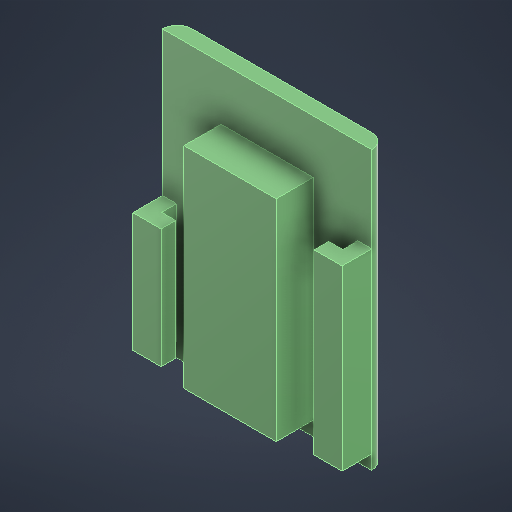
# Autodesk Inventor part: Tapa pulgar
Saved by Autodesk Inventor 2026 (Build 300175050, 175E)
## iProperties
Created: 2026-04-23
Part Number: Tapa pulgar
Material: Plástico ABS
Document SubType Name: Modeling
Designer: thepr
Density: 1.06 g/cm^3
Appearance: Suave - Verde bosque oscuro
Author: thepr
Autodesk Inventor part; units mm, degrees
ref_plane "YZ Plane" through (0, 0, 0) normal (1, 0, 0) x (0, 1, 0)
ref_plane "XZ Plane" through (0, 0, 0) normal (0, 1, 0) x (-1, 0, 0)
ref_plane "XY Plane" through (0, 0, 0) normal (0, 0, 1) x (1, 0, 0)
sketch "Boceto1" plane through (0, 0, 0) normal (0, 0, 1) x (1, 0, 0)
  line L0 (0, 0) -> (28.25, 0)
  line L1 (28.25, 0) -> (28.25, 37.5)
  line L2 (28.25, 37.5) -> (0, 37.5)
  line L3 (0, 37.5) -> (0, 0)
  line L4 (2, 37.5) -> (2, 0)
  line L5 (2, 2) -> (28.25, 2)
  line L6 (26.25, 37.5) -> (26.25, 2)
  line L7 (2, 35.5) -> (26.25, 35.5)
  dimension "d0" = 37.5
  dimension "d1" = 28.25
  dimension "d2" = 2
  dimension "d3" = 2
  dimension "d4" = 2
  dimension "d5" = 2
  constraints: 16 end point, 8 point on line, 5 perpendicular, 2 parallel, 1 horizontal
  measures "d0" distance of L2.end L0.start
  measures "d1" distance between parallel lines of L1 L3
  measures "d2" distance between parallel lines of L2 L7
  measures "d3" distance between parallel lines of L1 L6
  measures "d4" distance between parallel lines of L0 L5
  measures "d5" distance between parallel lines of L3 L4
extrude "Extrusión1" add sketch "Boceto1" along normal blind 2
sketch "Boceto2" plane through (0, 0, 0) normal (0, 0, -1) x (-1, 0, 0)
  line L0 (-28.25, 0) -> (-28.25, 37.5) projected
  line L1 (-28.25, 1.9) -> (0, 1.9)
  line L2 (0, 37.5) -> (0, 0) projected
  line L3 (0, 0) -> (-28.25, 0) projected
  line L4 (-26.25, 1.9) -> (-26.25, 25.9)
  line L5 (-26.25, 25.9) -> (-28.25, 25.9)
  line L6 (-2, 1.9) -> (-2, 18)
  line L7 (-2, 18) -> (0, 18)
  dimension "d8" = 1.9
  dimension "d9" = 2
  dimension "d10" = 2
  dimension "d11" = 24
  dimension "d12" = 16.1
  constraints: 10 end point, 6 point on line, 2 perpendicular, 2 vertical, 1 horizontal
  measures "d8" distance between parallel lines of L3 L1
  measures "d9" distance between parallel lines of L0 L4
  measures "d10" distance between parallel lines of L2 L6
  measures "d11" distance of L4.start L4.end
  measures "d12" distance of L6.start L6.end
extrude "Extrusión2" add sketch "Boceto2" against normal blind 6 contours L0 L5 L4 L1 | L1 L6 L7 L2
sketch "Boceto3" plane through (26.25, 1.9, 2) normal (-1, 0, 0) x (0, 0, 1)
  line L0 (4, 24) -> (4, 0) projected
  line L1 (0, 0) -> (0, 24) projected
  line L2 (0, 0) -> (4, 0) projected
  line L3 (4, 24) -> (4, 0) projected
  line L4 (0, 24) -> (4, 24) projected
  line L5 (0, 24) -> (4, 24) projected
  line L6 (2, 24) -> (2, 0)
  line L7 (0, 0) -> (4, 0) projected
  point P0 (-2, -1.9)
  point P1 (2, 24)
  point P2 (2, 0)
  dimension "d15" = 2
  constraints: 2 end point, 2 midpoint, 1 perpendicular
  measures "d15" distance between parallel lines of L0 L6
extrude "Extrusión3" add sketch "Boceto3" along normal blind 1.8 contours L0 L2 L6 L4
sketch "Boceto4" plane through (2, 1.9, 2) normal (1, 0, 0) x (0, 0, -1)
  line L0 (-2, 0) -> (-4, 0) projected
  line L1 (-4, 0) -> (-4, 24) projected
  line L2 (-4, 24) -> (-2, 24) projected
  line L3 (-2, 24) -> (-2, 0) projected
  line L4 (0, 16.1) -> (-4, 16.1) projected
  point P0 (2, -1.9)
  point P1 (-2, 16.1)
extrude "Extrusión4" add sketch "Boceto4" along normal blind 1.8 contours L0 L1 L4 L3
fillet "Empalme1" radius 2 2 edges at (28.25, 18.75, 0) (0, 18.75, 0)
sketch "Boceto5" plane through (0, 1.9, 6) normal (0, -1, 0) x (1, 0, 0)
  line L0 (2, -4) -> (0, -4) projected
  line L1 (2, -4) -> (2, -2) projected
  line L2 (2, -2) -> (3.8, -2) projected
  line L3 (3.8, 0) -> (3.8, -2) projected
  line L4 (0, 0) -> (3.8, 0) projected
  line L5 (0, -4) -> (0, 0) projected
  line L6 (28.25, -4) -> (26.25, -4) projected
  line L7 (28.25, -4) -> (28.25, 0) projected
  line L8 (28.25, 0) -> (24.45, 0) projected
  line L9 (24.45, -2) -> (24.45, 0) projected
  line L10 (26.25, -2) -> (24.45, -2) projected
  line L11 (26.25, -4) -> (26.25, -2) projected
  line L12 (2, -2) -> (1.9, -2)
  line L13 (1.9, -2) -> (1.9, -4)
  line L14 (0, -4) -> (2, -4) projected
  line L15 (26.25, -2) -> (24.45, -2) projected
  line L16 (26.25, -2) -> (26.35, -2)
  line L17 (26.35, -2) -> (26.35, -4)
  point P0 (0, -6)
  dimension "d21" = 0.1
  dimension "d22" = 0.1
  constraints: 8 end point, 2 horizontal, 2 perpendicular, 2 point on line
  measures "d21" distance between parallel lines of L1 L13
  measures "d22" distance between parallel lines of L11 L17
extrude "Extrusión5" cut sketch "Boceto5" against normal up to surface (35.6 mm away) contours L0 L13 L12 L1 | L6 L11 L16 L17
sketch "Boceto6" plane through (24.45, 1.9, 6) normal (0, -1, 0) x (1, 0, 0)
  arc A0 (-24.45, -4) -> (-22.45, -6) centre (-22.45, -4) ccw projected
  line L0 (-22.45, -6) -> (1.8, -6) projected
  arc A1 (1.8, -6) -> (3.8, -4) centre (1.8, -4) ccw projected
  line L1 (-24.45, -4) -> (3.8, -4) projected
  line L2 (-22.55, -4) -> (-22.55, -2) projected
  line L3 (-22.55, -2) -> (-20.65, -2) projected
  line L4 (-20.65, 0) -> (-20.65, -2) projected
  line L5 (-24.45, 0) -> (-20.65, 0) projected
  line L6 (-24.45, -4) -> (-24.45, 0) projected
  line L7 (-22.55, -4) -> (-24.45, -4) projected
  line L8 (1.9, -2) -> (1.9, -4) projected
  line L9 (3.8, -4) -> (1.9, -4) projected
  line L10 (3.8, -4) -> (3.8, 0) projected
  line L11 (3.8, 0) -> (0, 0) projected
  line L12 (0, -2) -> (0, 0) projected
  line L13 (0, -2) -> (1.9, -2) projected
  line L14 (3.8, -4) -> (-24.45, -4) projected
  line L15 (-16.55, -4) -> (-4.1, -4)
  line L16 (-4.1, -4) -> (-4.1, 1)
  line L17 (-4.1, 1) -> (-16.55, 1)
  line L18 (-16.55, 1) -> (-16.55, -4)
  point P0 (-24.45, -6)
  dimension "d25" = 5
  dimension "d26" = 6
  dimension "d27" = 6
  constraints: 8 end point, 2 parallel, 1 horizontal, 1 perpendicular, 1 point on line
  measures "d25" distance between parallel lines of L1 L17
  measures "d26" distance between parallel lines of L16 L8
  measures "d27" distance between parallel lines of L2 L18
extrude "Extrusión6" add sketch "Boceto6" against normal blind 21.1 contours L18 L17 L16 L1
move faces "Desplazar1" translate (0, 7.3, 0) faces at (16.2, 23, 3.6667)
